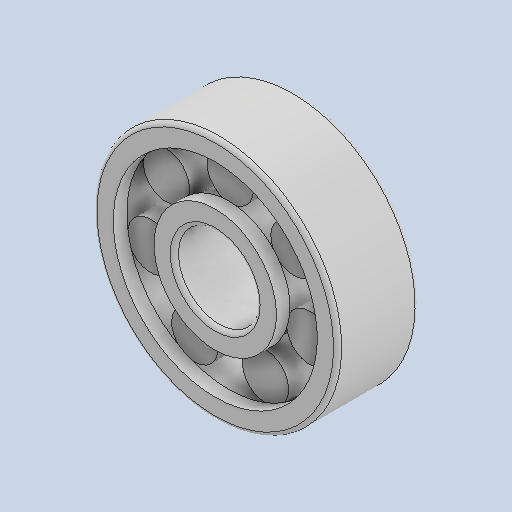
# Autodesk Inventor part: cuscinetto_wheel
Saved by Autodesk Inventor 2026.1 (Build 301233020, 233B)
## iProperties
Created: 2026-01-06
Part Number: cuscinetto_wheel
Material: Generico
Document SubType Name: Modeling
Designer: maxbu
Density: 1 g/cm^3
Appearance: Default
Author: maxbu
Autodesk Inventor part; units mm, degrees
ref_plane "YZ Plane" through (0, 0, 0) normal (1, 0, 0) x (0, 1, 0)
ref_plane "XZ Plane" through (0, 0, 0) normal (0, 1, 0) x (-1, 0, 0)
ref_plane "XY Plane" through (0, 0, 0) normal (0, 0, 1) x (1, 0, 0)
sketch "Schizzo1" plane through (0, 0, 0) normal (1, 0, 0) x (0, 1, 0)
  line L0 (0, 0) -> (3, 0) construction
  line L1 (3, 0) -> (3, -6)
  line L2 (3, -6) -> (4.5, -6)
  line L3 (4.5, 0) -> (3, 0)
  line L4 (4.5, 0) -> (7.5, 0) construction
  line L5 (7.5, -6) -> (9, -6)
  line L6 (9, -6) -> (9, 0)
  line L7 (7.5, 0) -> (9, 0)
  line L8 (4.5, -1) -> (4.3, -1)
  line L9 (4.3, -1) -> (4.3, -5)
  line L10 (4.3, -5) -> (4.5, -5)
  line L11 (6, 0) -> (6, -6) construction
  line L12 (6, -6) -> (7.5, -6) construction
  line L13 (7.5, -1) -> (7.7, -1)
  line L14 (7.7, -1) -> (7.7, -5)
  line L15 (7.7, -5) -> (7.5, -5)
  line L16 (4.5, 0) -> (4.5, -1)
  line L17 (4.5, -5) -> (4.5, -6)
  line L18 (7.5, -1) -> (7.5, 0)
  line L19 (7.5, -5) -> (7.5, -6)
  line L20 (0, 0) -> (0, -6) construction
  line L21 (0, -6) -> (3, -6) construction
  dimension "d0" = 3
  dimension "d1" = 6
  dimension "d2" = 1.5
  dimension "d3" = 9
  dimension "d4" = 0.2
  dimension "d5" = 4
  constraints: 44 end point, 7 vertical, 6 horizontal, 5 collinear, 4 perpendicular, 4 symmetric about line, 2 point on line, 1 midpoint
  measures "d0" distance from line of L0.start L1
  measures "d1" distance of L0.end L1.end
  measures "d2" distance of L1.end L2.end
  measures "d3" distance from line of L0.start L6
  measures "d4" distance of L8.start L8.end
  measures "d5" distance of L8.end L9.end
revolve "Rivoluzione1" add sketch "Schizzo1" angle 360 about axis through (0, 0, 0) along (0, 0, -1)
sketch "Schizzo2" plane through (0, 0, 0) normal (1, 0, 0) x (0, 1, 0)
  line L0 (0, 0) -> (0, -1.1)
  line L1 (0, -1.1) -> (5.9995, -1.1) construction
  line L2 (5.9995, -1.1) -> (7.699, -1.1)
  line L3 (7.699, -1.1) -> (7.699, -4.9)
  line L4 (7.699, -4.9) -> (5.9995, -4.9)
  line L5 (7.7, -5) -> (7.7, -1) projected
  line L6 (7.7, -3) -> (7.699, -3)
  line L7 (-7.7, -1) -> (7.7, -1) projected
  line L8 (-7.7, -5) -> (7.7, -5) projected
  line L9 (4.3, -1) -> (4.3, -5) projected
  line L10 (7.699, -4.9) -> (4.3, -4.9) construction
  line L11 (5.9995, -4.9) -> (5.9995, -1.1)
  dimension "d10" = 0.001
  dimension "d11" = 0.1
  constraints: 17 end point, 4 perpendicular, 3 midpoint, 2 horizontal, 2 point on line, 1 vertical
  measures "d10" distance between parallel lines of L3 L5
  measures "d11" distance between parallel lines of L7 L2
revolve "Rivoluzione2" add sketch "Schizzo2" angle 360 about axis through (0, 5.9995, -4.9) along (0, 0, 1) contours L2 L3 L4 L11
pattern_circular "Serie circolare1" count 7 over 360 about axis through (0, 0, -3) along (0, 0, -1) of "Rivoluzione2"
fillet "Raccordo1" radius 0.3 4 edges at (0, -9, -6) (0, -9, 0) (0, -3, -6) (0, -3, 0)
